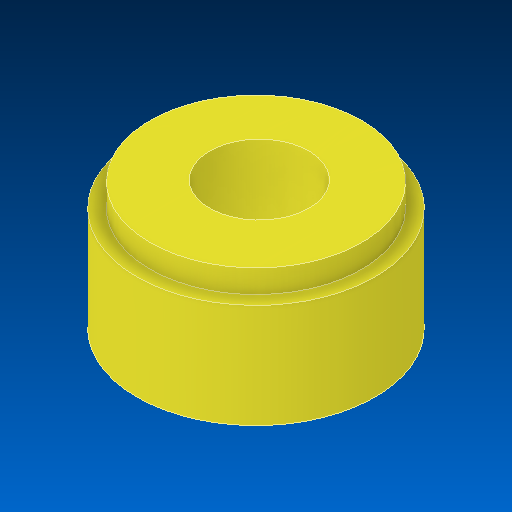
# Autodesk Inventor part: pump filter
Saved by Autodesk Inventor 2019 (Build 230136000, 136)
## iProperties
Created: 2019-03-13
Part Number: pump filter
Material: Generic
Document SubType Name: Modeling
Designer: Dell
Density: 1 g/cm^3
Appearance: Canary
Mass: 124.282 g
Surface Area: 189.374 cm^2
Volume: 124.282 cm^3
Author: Dell
Autodesk Inventor part; units mm, degrees
ref_plane "YZ Plane" through (0, 0, 0) normal (1, 0, 0) x (0, 1, 0)
ref_plane "XZ Plane" through (0, 0, 0) normal (0, 1, 0) x (-1, 0, 0)
ref_plane "XY Plane" through (0, 0, 0) normal (0, 0, 1) x (1, 0, 0)
sketch "Sketch1" plane through (0, 0, 0) normal (1, 0, 0) x (0, 1, 0)
  line L0 (42.7803, 1) -> (-48.3438, 1)
  line L1 (-6.1361, 33) -> (-13.1361, 33)
  line L2 (-13.1361, 33) -> (-13.1361, 37)
  line L3 (-13.1361, 37) -> (-44.6361, 37)
  line L4 (-44.6361, 37) -> (-45.4918, 1)
  line L5 (-6.1361, 33) -> (-6.1361, 1)
  point P0 (0, 0)
  dimension "d0" = 32
  dimension "d2" = 7
  dimension "d3" = 31.5
  dimension "d5" = 36
  constraints: 12 end point, 3 perpendicular, 2 horizontal, 2 point on line
  measures "d0" distance between parallel lines of L1 L0
  measures "d2" distance of L1.start L1.end
  measures "d3" distance of L2.end L3.end
  measures "d5" distance between parallel lines of L3 L0
revolve "Revolution1" add sketch "Sketch1" angle 360 about axis through (0, 42.7803, 1) along (0, -1, 0)
sketch "Sketch2" plane through (0, -6.1361, 1) normal (0, 1, 0) x (1, 0, 0)
  circle A0 centre (0, 1) radius 15
  dimension "d6" = 30
  constraints: 1 centre point, 1 coincident
  measures "d6" diameter of A0
extrude "Extrusion1" cut sketch "Sketch2" against normal through all
body "Solid1"
